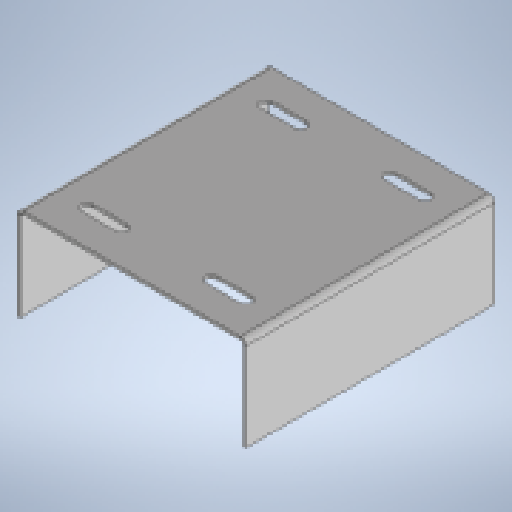
# Autodesk Inventor part: DMF-4101 Gearbox Stand 01
Saved by Autodesk Inventor 2026.2 (Build 302298000, 298)
## iProperties
Created: 2026-06-04
Part Number: DMF-4101 Gearbox Stand 01
Material: Stainless Steel
Description: DIE16(5)|\ 90°|corrY -___°|X_____|bom___
Document SubType Name: Sheet Metal
Designer: admin
Stock Number: DMF-4101-01
Mass: 1762.25 g
Surface Area: 2283.33 cm^2
Volume: 220.281 cm^3
Density: 8 g/cm^3
Sheet Metal Rule: AISI304 2mm Die16
Sheet Metal Width: 409,786 mm
Sheet Metal Length: 250,000 mm
Sheet Metal Area: 102446,571 mm^2
Appearance: Default
Flat Pattern Width: 40.9786 cm
Flat Pattern Length: 25 cm
Flat Pattern Area: 1024.47 cm^2
Author: admin
Autodesk Inventor part; units mm, degrees
ref_plane "YZ Plane" through (0, 0, 0) normal (1, 0, 0) x (0, 1, 0)
ref_plane "XZ Plane" through (0, 0, 0) normal (0, 1, 0) x (-1, 0, 0)
ref_plane "XY Plane" through (0, 0, 0) normal (0, 0, 1) x (1, 0, 0)
sketch "Sketch1" plane through (0, 0, 0) normal (0, 0, 1) x (1, 0, 0)
  line L0 (-150, -125) -> (150, -125)
  line L1 (150, -125) -> (150, 125)
  line L2 (150, 125) -> (-150, 125)
  line L3 (-150, 125) -> (-150, -125)
  line L4 (-150, -125) -> (150, 125) construction
  line L5 (150, -125) -> (-150, 125) construction
  line L6 (0, 125) -> (0, -125) construction
  line L7 (-150, 0) -> (150, 0) construction
  line L8 (-80, -90) -> (-45, -90) construction
  line L9 (-80, -96) -> (-45, -96)
  line L10 (-45, -84) -> (-80, -84)
  arc A0 (-80, -84) -> (-80, -96) centre (-80, -90) ccw
  arc A1 (-45, -96) -> (-45, -84) centre (-45, -90) ccw
  line L11 (80, -90) -> (45, -90) construction
  line L12 (80, -84) -> (45, -84)
  line L13 (45, -96) -> (80, -96)
  arc A2 (80, -96) -> (80, -84) centre (80, -90) ccw
  arc A3 (45, -84) -> (45, -96) centre (45, -90) ccw
  line L14 (80, 90) -> (45, 90) construction
  line L15 (80, 96) -> (45, 96)
  line L16 (45, 84) -> (80, 84)
  arc A4 (80, 84) -> (80, 96) centre (80, 90) ccw
  arc A5 (45, 96) -> (45, 84) centre (45, 90) ccw
  line L17 (-45, 90) -> (-80, 90) construction
  line L18 (-45, 96) -> (-80, 96)
  line L19 (-80, 84) -> (-45, 84)
  arc A6 (-45, 84) -> (-45, 96) centre (-45, 90) ccw
  arc A7 (-80, 96) -> (-80, 84) centre (-80, 90) ccw
  point P0 (0, 0)
  point P1 (62.5, -90)
  point P2 (62.5, 90)
  point P3 (-62.5, 90)
  point P4 (-62.5, -90)
  dimension "d154" = 300
  dimension "d155" = 250
  dimension "d200" = 6
  dimension "d201" = 35
  dimension "d202" = 125
  dimension "d203" = 35
  dimension "d204" = 35
  measures "d154" distance of L1.end L2.end
  measures "d155" distance of L0.end L1.end
  measures "d200" radius of A2
  measures "d201" distance of L11.start L11.end
  measures "d202" distance of point (-62.5, -90) point (62.5, -90)
  measures "d203" distance between parallel lines of L11 L0
  measures "d204" distance between parallel lines of L2 L14
extrude "Plate5" add sketch "Sketch1" along normal blind 3
sketch "Sketch10" plane through (147, -125, 3) normal (1, 0, 0) x (0, 1, 0)
  line L0 (250, 0) -> (0, 0)
  line L1 (0, 0) -> (0, -60)
  line L2 (0, -60) -> (250, -60)
  line L3 (250, -60) -> (250, 0)
  constraints: 6 end point, 1 horizontal, 1 perpendicular, 1 vertical
edge flange "Flange5" height 60 angle 90 thickness 3 bend radius 2.75 thickness toward (1, 0, 0) relief round relief width 3 relief depth 1.5 corner gap 2.75 corner form 0 edges at (150, 0, 0) (-150, 0, 0) wall of the first edge with corners at (147, 125, 3) (147, -125, 3) (147, -125, -57) (147, 125, -57)
bend "Bend5"
corner "Corner5"
body "Solid3"
